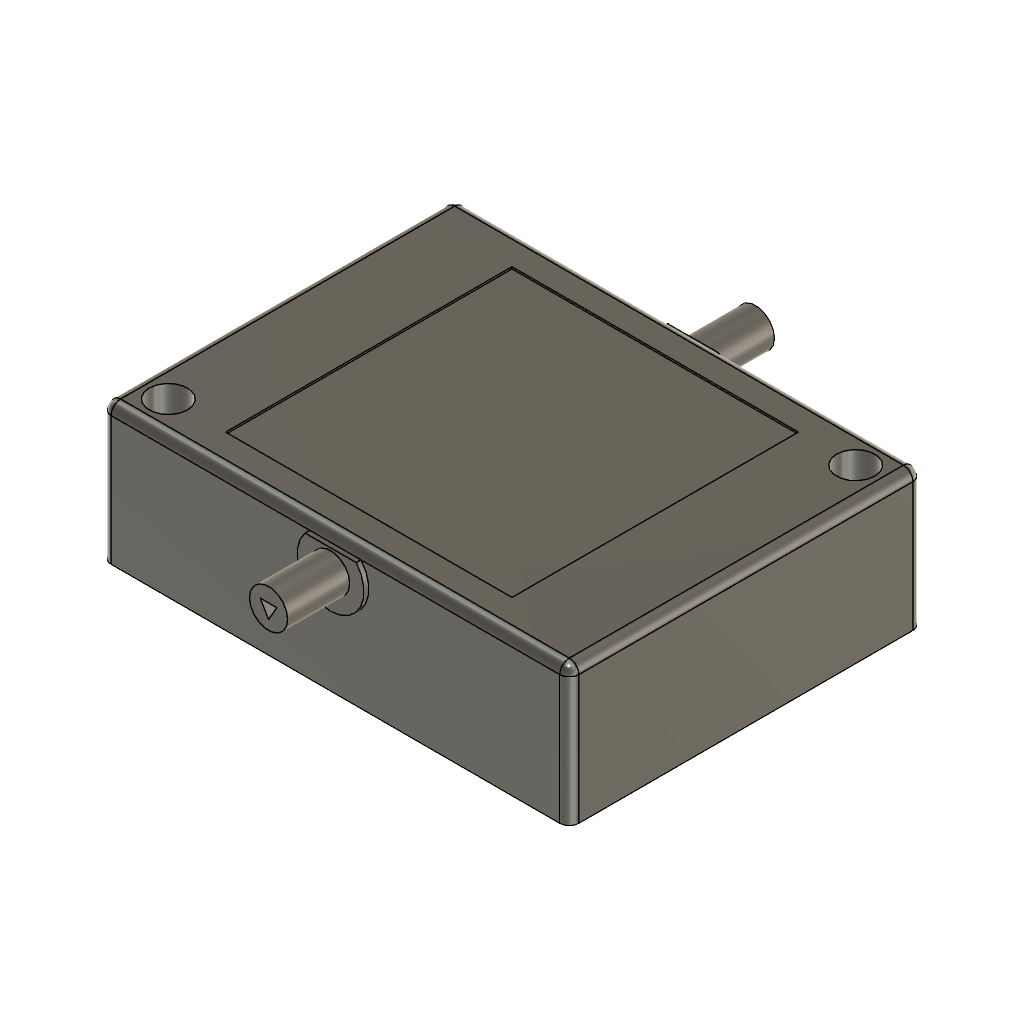
CasePart3 (Autodesk Fusion 360 design; units mm, degrees)
part number: 2026-10-03-21-02-19-954
Autodesk Fusion 360 part; units mm, degrees
sketch "Szkic1" plane through (0, 0, 0) normal (0, 0, 1) x (1, 0, 0)
  line L0 (0, 0) -> (49, 0)
  line L1 (49, 0) -> (49, 37)
  line L2 (49, 37) -> (0, 37)
  line L3 (0, 37) -> (0, 0)
  constraint horizontal L0
  constraint vertical L1
  constraint horizontal L2
  constraint vertical L3
  constraint coincident L0.start L3.end
extrude "Wyciągnięcie proste1" add sketch "Szkic1" along normal blind 2
sketch "Szkic2" plane through (0, 0, 0) normal (0, 0, -1) x (1, 0, 0)
  line L0 (0, 0) -> (0, -37)
  line L1 (0, -37) -> (49, -37)
  line L2 (49, -37) -> (49, 0)
  line L3 (49, 0) -> (0, 0)
  line L4 (0, 0) -> (49, 0)
  line L5 (49, 0) -> (49, -37)
  line L6 (49, -37) -> (42, -37)
  line L7 (0, -37) -> (0, 0)
  line L8 (7, -2) -> (47, -2)
  line L9 (47, -2) -> (47, -30)
  line L10 (42, -35) -> (2, -35)
  line L11 (2, -35) -> (14, -35)
  line L12 (12.5, -15) -> (2, -15)
  line L13 (2, -15) -> (2, -35)
  line L14 (47, -2) -> (35, -2)
  line L15 (36.5, -22) -> (47, -22)
  line L16 (47, -22) -> (47, -2)
  line L17 (2, -15) -> (12.5, -15)
  line L18 (13, -35) -> (2, -35)
  line L19 (2, -35) -> (2, -15)
  line L20 (47, -2) -> (36, -2)
  line L21 (36.5, -22) -> (47, -22)
  line L22 (47, -22) -> (47, -2)
  line L23 (12.5, -15) -> (12.5, -26.5)
  line L24 (36.5, -2) -> (36.5, -22)
  line L25 (0, 0) -> (7, 0)
  line L26 (7, 0) -> (7, -7)
  line L27 (7, -7) -> (0, -7)
  line L28 (0, -7) -> (0, 0)
  line L29 (2, -35) -> (2, -7)
  line L30 (49, -37) -> (42, -37)
  line L31 (42, -37) -> (42, -30)
  line L32 (42, -30) -> (49, -30)
  line L33 (49, -30) -> (49, -37)
  line L34 (19.5, -28.5) -> (19.5, -28.5)
  line L35 (19.5, -30.5) -> (19.5, -30.5)
  line L36 (12.5, -26.5) -> (12.5, -28.5)
  line L37 (12.5, -28.5) -> (12.5, -30.5)
  line L38 (12.5, -30.5) -> (19.5, -30.5)
  line L39 (29.5, -30.5) -> (35, -30.5)
  line L40 (29.5, -30.5) -> (37, -30.5)
  line L41 (2, -35) -> (21, -35)
  line L42 (49, -37) -> (42, -37)
  line L43 (19.5, -30.5) -> (19.5, -35)
  line L44 (37, -30.5) -> (38, -30.5)
  line L45 (38, -30.5) -> (38, -35)
  line L46 (29.5, -35) -> (29.5, -30.5)
  line L47 (19.5, -5.5) -> (36.5, -5.5)
  line L48 (19.5, -5.5) -> (12.5, -5.5)
  line L49 (12.5, -2) -> (13.5, -2)
  line L50 (13.5, -5.5) -> (17, -5.5)
  line L51 (18, -5.5) -> (21.5, -5.5)
  line L52 (22.5, -5.5) -> (26, -5.5)
  line L53 (27, -5.5) -> (30.5, -5.5)
  line L54 (27, -5.5) -> (30.5, -5.5)
  line L55 (31.5, -5.5) -> (35, -5.5)
  line L56 (13, -5.5) -> (12.5, -5.5)
  line L57 (30, -5.5) -> (24.5, -5.5)
  line L58 (31.5, -2) -> (31.5, -4.5)
  line L59 (30.5, -2) -> (30.5, -4.5)
  line L60 (25.5, -2) -> (25.5, -4.5)
  line L61 (24.5, -2) -> (24.5, -4.5)
  line L62 (19.5, -2) -> (19.5, -4.5)
  line L63 (18.5, -2) -> (18.5, -4.5)
  line L64 (12.5, -2) -> (12.5, -5.5)
  line L65 (13.5, -2) -> (13.5, -4.5)
  line L66 (13.5, -2) -> (15, -2)
  line L67 (13.5, -2) -> (16, -2)
  line L68 (16, -2) -> (15.5, -2)
  line L69 (16, -2) -> (16.5, -2)
  line L70 (16.5, -2) -> (16.5, -4.5)
  line L71 (15.5, -4.5) -> (15.5, -2)
  line L72 (19.5, -2) -> (21.5, -2)
  line L73 (21.5, -4.5) -> (21.5, -2)
  line L74 (22.5, -2) -> (22.5, -4.5)
  line L75 (25.5, -2) -> (27.5, -2)
  line L76 (27.5, -4.5) -> (27.5, -2)
  line L77 (28.5, -4.5) -> (28.5, -2)
  line L78 (31.5, -2) -> (33.5, -2)
  line L79 (33.5, -2) -> (33.5, -4.5)
  line L80 (34.5, -4.5) -> (34.5, -2)
  line L81 (13.5, -4.5) -> (15.5, -4.5)
  line L82 (16.5, -4.5) -> (18.5, -4.5)
  line L83 (19.5, -4.5) -> (21.5, -4.5)
  line L84 (22.5, -4.5) -> (24.5, -4.5)
  line L85 (25.5, -4.5) -> (27.5, -4.5)
  line L86 (28.5, -4.5) -> (30.5, -4.5)
  line L87 (31.5, -4.5) -> (33.5, -4.5)
  line L88 (34.5, -4.5) -> (36.5, -4.5)
  constraint horizontal L4
  constraint vertical L5
  constraint horizontal L6
  constraint vertical L7
  constraint coincident L1.end L2.start
  constraint coincident L0.start L3.end
  constraint horizontal L8
  constraint vertical L9
  constraint horizontal L10
  constraint vertical L29
  constraint horizontal L11
  constraint horizontal L12
  constraint vertical L13
  constraint horizontal L14
  constraint horizontal L15
  constraint vertical L16
  constraint horizontal L17
  constraint horizontal L18
  constraint vertical L19
  constraint coincident L11 L18.start
  constraint horizontal L20
  constraint horizontal L21
  constraint vertical L22
  constraint perpendicular L11 L23
  constraint coincident L14 L24.start
  constraint perpendicular L15 L24
  constraint horizontal L25
  constraint vertical L26
  constraint horizontal L27
  constraint vertical L28
  constraint coincident L27 L29.end
  constraint coincident L26 L8.start
  constraint horizontal L30
  constraint vertical L31
  constraint horizontal L32
  constraint vertical L33
  constraint coincident L31 L10.start
  constraint coincident L32 L9.end
  constraint horizontal L38
  constraint collinear L38 L39
  constraint coincident L10 L41.end
  constraint coincident L41 L43.end
  constraint coincident L10 L45.end
  constraint perpendicular L10 L45
  constraint coincident L10 L46.start
  constraint coincident L24 L47.end
  constraint perpendicular L24 L47
  constraint coincident L8 L49.start
  constraint coincident L8 L49.end
  constraint coincident L48 L50.start
  constraint coincident L48 L50.end
  constraint coincident L48 L51.start
  constraint coincident L47 L51.end
  constraint coincident L47 L52.start
  constraint coincident L47 L52.end
  constraint coincident L47 L53.start
  constraint coincident L47 L53.end
  constraint coincident L47 L55.start
  constraint coincident L47 L55.end
  constraint coincident L48 L56.start
  constraint coincident L53 L57.start
  constraint coincident L52 L57.end
  constraint coincident L8 L58.start
  constraint perpendicular L55 L58
  constraint coincident L8 L59.start
  constraint perpendicular L54 L59
  constraint coincident L8 L60.start
  constraint coincident L8 L61.start
  constraint perpendicular L52 L61
  constraint coincident L8 L62.start
  constraint perpendicular L8 L62
  constraint coincident L8 L63.start
  constraint perpendicular L48 L64
  constraint perpendicular L48 L65
  constraint perpendicular L63 L82
  constraint perpendicular L61 L84
  constraint perpendicular L59 L86
  constraint coincident L24 L88.end
  constraint perpendicular L24 L88
  constraint coincident L8 L66.end
  constraint perpendicular L63 L66
  constraint coincident L8 L67.end
  constraint coincident L67 L68.end
  constraint coincident L8 L69.end
  constraint perpendicular L70 L82
  constraint perpendicular L67 L71
  constraint coincident L8 L72.end
  constraint perpendicular L72 L73
  constraint coincident L8 L74.start
  constraint perpendicular L74 L84
  constraint coincident L8 L75.end
  constraint perpendicular L60 L75
  constraint perpendicular L75 L76
  constraint coincident L8 L77.end
  constraint perpendicular L8 L77
  constraint coincident L8 L78.end
  constraint perpendicular L79 L87
  constraint coincident L8 L80.end
  constraint perpendicular L8 L80
  constraint collinear L81 L82
  constraint collinear L83 L84
  constraint collinear L85 L86
  constraint collinear L87 L88
extrude "Wyciągnięcie proste2" add sketch "Szkic2" along normal blind 12.5 contours L0 L3 L4 L7 L25 L26 L27 L28 | L0 L1 L7 L10 L11 L13 L18 L19 L27 L29 L31 L41 | L2 L3 L4 L5 L8 L9 L14 L16 L20 L22 L26 L32 L49 L66 L67 L68 L69 L72 L75 L78 | L1 L2 L5 L6 L30 L31 L32 L33 L42 | L10 L11 L12 L13 L17 L18 L19 L23 L29 L36 L37 L38 L41 L43 | L8 L24 L47 L48 L49 L50 L51 L52 L53 L54 L55 L56 L57 L58 L59 L60 L61 L62 L63 L64 L65 L67 L68 L69 L70 L71 L73 L74 L76 L77 L79 L80 L81 L82 L83 L84 L85 L86 L87 L88 | L10 L39 L40 L44 L45 L46 | L8 L9 L14 L15 L16 L20 L21 L22 L24
sketch "Szkic8" plane through (0, 0, 2) normal (0, 0, 1) x (-1, 0, 0)
  line L0 (0, -37) -> (0, 0)
  line L1 (0, 0) -> (-49, 0)
  line L2 (-49, 0) -> (-49, -37)
  line L3 (-49, -37) -> (0, -37)
  line L4 (-49, -37) -> (-45.5, -37)
  line L5 (-45.5, -37) -> (-45.5, -33.5)
  line L6 (0, 0) -> (-3.5, 0)
  line L7 (-3.5, 0) -> (-3.5, -3.5)
  circle A0 centre (-3.5, -3.5) radius 2
  circle A1 centre (-45.5, -33.5) radius 2
  dimension "d17" = 4
  dimension "d18" = 4
  constraint coincident L2.end L3.start
  constraint coincident L3 L4.end
  constraint perpendicular L4 L5
  constraint coincident L0.end L1.start
  constraint coincident L1 L6.end
  constraint perpendicular L1 L7
  constraint coincident L7.end A0.centre
  constraint coincident L5.end A1.centre
  measures "d17" diameter of A0
  measures "d18" diameter of A1
extrude "Wyciągnięcie proste6" cut sketch "Szkic8" against normal blind 14 contours A0 | A1
sketch "Szkic13" plane through (0, 37, 0) normal (0, 1, 0) x (-1, 0, 0)
  line L0 (0, 2) -> (-49, 2)
  line L1 (-49, -12.5) -> (0, -12.5)
  line L2 (0, -12.5) -> (-24.5, -12.5)
  line L3 (-24.5, -12.5) -> (-24.5, -9.5)
  line L4 (-24.5, -12.5) -> (-24.5, -9.5)
  line L5 (-24.5, -9.5) -> (-28.75, -9.5)
  line L6 (-28.75, -9.5) -> (-24.5, -9.5)
  line L7 (-24.5, -9.5) -> (-20, -9.5)
  line L8 (-49, -12.5) -> (-24.5, -12.5)
  line L9 (-24.5, -9.5) -> (-29.5, -9.5)
  line L10 (-29.5, -9.5) -> (-29.5, -4.5)
  line L11 (-19.5, -9.5) -> (-19.5, -4.5)
  line L12 (-19.5, -4.5) -> (-20.25, -4.5)
  line L13 (-29.5, -4.5) -> (-20.25, -4.5)
  line L14 (-20, -9.5) -> (-19.5, -9.5)
  line L15 (0, -12.5) -> (0, 2)
  line L16 (-49, 2) -> (-49, -12.5)
  constraint midpoint L1 L2.end
  constraint perpendicular L1 L3
  constraint perpendicular L4 L5
  constraint perpendicular L4 L7
  constraint perpendicular L4 L9
  constraint perpendicular L5 L10
  constraint perpendicular L10 L13
  constraint perpendicular L11 L14
extrude "Wyciągnięcie proste11" cut sketch "Szkic13" against normal blind 2 contours L5 L6 L7 L9 L10 L11 L12 L13 L14
sketch "Szkic15" plane through (0, 0, -12) normal (0, 0, 1) x (-1, 0, 0)
  circle A0 centre (-3.5, -3.5) radius 2
  circle A1 centre (-3.5, -3.5) radius 1.5
  circle A2 centre (-45.5, -33.5) radius 1.5
  dimension "d39" = 3
  dimension "d40" = 3
  constraint concentric A0 A1
  measures "d39" diameter of A1
  measures "d40" diameter of A2
extrude "Wyciągnięcie proste13" cut sketch "Szkic15" against normal blind 1 contours A1 | A2
sketch "Szkic16" plane through (0, 37, 0) normal (0, 1, 0) x (-1, 0, 0)
  line L0 (-19.5, -4.5) -> (-19.5, -9.5)
  line L1 (-19.5, -9.5) -> (-29.5, -9.5)
  line L2 (-29.5, -9.5) -> (-29.5, -4.5)
  line L3 (-29.5, -4.5) -> (-19.5, -4.5)
  line L4 (0, 2) -> (-49, 2)
  line L5 (-49, -12.5) -> (0, -12.5)
  line L6 (-49, 2) -> (-24.5, 2)
  line L7 (-24.5, 2) -> (-24.5, -1.25)
  circle A0 centre (-24.5, -1.25) radius 2
  line L8 (0, -12.5) -> (0, 2)
  line L9 (-49, 2) -> (-49, -12.5)
  dimension "d47" = 24.5
  dimension "d48" = 3.25
  dimension "d49" = 4
  constraint perpendicular L3 L7
  constraint coincident L7.end A0.centre
  measures "d47" distance of L4.end L6.end
  measures "d48" distance of L6.end L7.end
  measures "d49" diameter of A0
extrude "Wyciągnięcie proste14" add sketch "Szkic16" along normal blind 7 contours A0
sketch "Szkic17" plane through (0, 0, 0) normal (0, -1, 0) x (1, 0, 0)
  line L0 (49, 2) -> (0, 2)
  line L1 (0, -12.5) -> (49, -12.5)
  line L2 (0, 2) -> (24.5, 2)
  line L3 (24.5, 2) -> (24.5, -1.25)
  circle A0 centre (24.5, -1.25) radius 2
  line L4 (49, -12.5) -> (49, 2)
  line L5 (0, 2) -> (0, -12.5)
  dimension "d52" = 24.5
  dimension "d53" = 3.25
  dimension "d54" = 4
  constraint perpendicular L2 L3
  constraint coincident L3.end A0.centre
  measures "d52" distance of L0.end L2.end
  measures "d53" distance of L2.end L3.end
  measures "d54" diameter of A0
extrude "Wyciągnięcie proste15" add sketch "Szkic17" along normal blind 7 contours A0
sketch "Szkic11" plane through (0, 0, 2) normal (0, 0, 1) x (-1, 0, 0)
  circle A0 centre (-3.5, -3.5) radius 2
  circle A1 centre (-45.5, -33.5) radius 2
  line L0 (0, -37) -> (0, 0)
  line L1 (0, 0) -> (-49, 0)
  line L2 (-49, 0) -> (-49, -37)
  line L3 (-49, -37) -> (0, -37)
  line L4 (0, 0) -> (-24.5, 0)
  line L5 (-24.5, 0) -> (-24.5, -3.5)
  line L6 (-9.5, -33) -> (-9.5, -33)
  line L7 (-10, -33) -> (-10, -33)
  line L8 (-9.5, -33) -> (-9.5, -33.5)
  line L9 (-9.5, -33.5) -> (-39.5, -33.5)
  line L10 (-39.5, -33.5) -> (-39.5, -3.5)
  line L11 (-39.5, -3.5) -> (-9.5, -3.5)
  line L12 (-9.5, -3.5) -> (-9.5, -33.5)
  constraint coincident L0.end L1.start
  constraint midpoint L1 L4.end
  constraint perpendicular L4 L5
  constraint horizontal L9
  constraint vertical L10
  constraint horizontal L11
  constraint vertical L12
  constraint coincident L11 L5.end
extrude "Wyciągnięcie proste9" cut sketch "Szkic11" against normal blind 0.2 contours L8 L9 L10 L11 L12
sketch "Szkic18" plane through (0, 44, 0) normal (0, 1, 0) x (-1, 0, 0)
  circle A0 centre (-24.5, -1.25) radius 2
  circle A1 centre (-24.5, -1.25) radius 2
  circle A2 centre (-24.5, -1.25) radius 1
  line L0 (-24.5, -1.25) -> (-24.5, -2.25)
  line L1 (-24.5, -2.25) -> (-25.3652, -0.7485)
  line L2 (-24.5, -2.25) -> (-23.6348, -0.7485)
  line L3 (-25.3652, -0.7485) -> (-23.6348, -0.7485)
  dimension "d57" = 2
  constraint concentric A0 A1
  constraint concentric A1 A2
  constraint coincident A0.centre A1.centre
  constraint coincident A2 L0.end
  constraint vertical L0
  constraint coincident A2 L1.end
  constraint coincident A2 L2.end
  constraint horizontal L3
  measures "d57" diameter of A2
extrude "Wyciągnięcie proste16" cut sketch "Szkic18" against normal blind 3 contours L1 L2 L3
sketch "Szkic19" plane through (0, -7, 0) normal (0, -1, 0) x (1, 0, 0)
  circle A0 centre (24.5, -1.25) radius 2
  circle A1 centre (24.5, -1.25) radius 2
  circle A2 centre (24.5, -1.25) radius 1
  line L0 (24.5, -1.25) -> (24.5, -2.25)
  line L1 (24.5, -2.25) -> (25.366, -0.7499)
  line L2 (24.5, -2.25) -> (23.634, -0.7499)
  line L3 (23.634, -0.7499) -> (25.366, -0.7499)
  dimension "d60" = 2
  constraint concentric A0 A1
  constraint concentric A1 A2
  constraint coincident A0.centre A1.centre
  constraint coincident A2 L0.end
  constraint vertical L0
  constraint coincident A2 L1.end
  constraint coincident A2 L2.end
  constraint horizontal L3
  measures "d60" diameter of A2
extrude "Wyciągnięcie proste17" cut sketch "Szkic19" against normal blind 3 contours L1 L2 L3
fillet "Zaokrąglenie2" radius 1 8 edges at (0, 37, -5.25) (0, 0, -5.25) (0, 18.5, 2) (24.5, 37, 2) (49, 37, -5.25) (49, 18.5, 2) (24.5, 0, 2) (49, 0, -5.25)
sketch "Szkic20" plane through (0, 0, 0) normal (0, -1, 0) x (1, 0, 0)
  line L0 (48, -12.5) -> (48, 1)
  line L1 (48, 1) -> (1, 1)
  line L2 (1, 1) -> (1, -12.5)
  line L3 (1, -12.5) -> (48, -12.5)
  circle A0 centre (24.5, -1.25) radius 2
  circle A1 centre (24.5, -1.25) radius 3.5
  dimension "d66" = 7
  measures "d66" diameter of A1
extrude "Wyciągnięcie proste18" add sketch "Szkic20" along normal blind 0.5 contours L1 A1 picked at (22.0612, 0.4859)
sketch "Szkic21" plane through (0, 37, 0) normal (0, 1, 0) x (-1, 0, 0)
  line L0 (-48, 1) -> (-48, -12.5)
  line L1 (-48, -12.5) -> (-1, -12.5)
  line L2 (-1, -12.5) -> (-1, 1)
  line L3 (-1, 1) -> (-48, 1)
  circle A0 centre (-24.5, -1.25) radius 2
  line L4 (-19.5, -4.5) -> (-19.5, -9.5)
  line L5 (-19.5, -9.5) -> (-29.5, -9.5)
  line L6 (-29.5, -9.5) -> (-29.5, -4.5)
  line L7 (-29.5, -4.5) -> (-19.5, -4.5)
  circle A1 centre (-24.5, -1.25) radius 3.5
  dimension "d69" = 7
  constraint concentric A0 A1
  measures "d69" diameter of A1
extrude "Wyciągnięcie proste19" add sketch "Szkic21" along normal blind 0.5 contours L3 L7 A1
equation "d47 = ( 49.000 / 2 ) * 1 mm"
equation "d48 = ( 6.500 / 2 ) * 1 mm"
equation "d52 = ( 49.000 / 2 ) * 1 mm"
